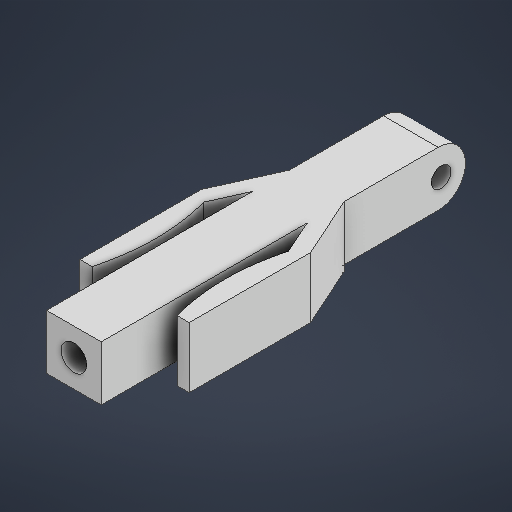
# Autodesk Inventor part: Upper leg connector to UL Ring_4
Saved by Autodesk Inventor 2027 (Build 310192060, 192F)
## iProperties
Created: 2026-07-03
Part Number: Upper leg connector to UL Ring_4
Material: Generic
Document SubType Name: Modeling
Designer: troop
Density: 1 g/cm^3
Appearance: Default
Author: troop
Autodesk Inventor part; units mm, degrees
ref_plane "YZ Plane" through (0, 0, 0) normal (1, 0, 0) x (0, 1, 0)
ref_plane "XZ Plane" through (0, 0, 0) normal (0, 1, 0) x (-1, 0, 0)
ref_plane "XY Plane" through (0, 0, 0) normal (0, 0, 1) x (1, 0, 0)
sketch "Sketch1" plane through (0, 0, 0) normal (0, 0, 1) x (1, 0, 0)
  line L0 (0, 0) -> (11.43, 0)
  line L1 (11.43, 0) -> (11.43, 11.43)
  line L2 (11.43, 11.43) -> (0, 11.43)
  line L3 (0, 11.43) -> (0, 0)
  dimension "d0" = 11.43
  dimension "d1" = 11.43
  constraints: 8 end point, 2 parallel, 1 horizontal, 1 perpendicular
  measures "d0" distance of L1.end L2.end
  measures "d1" distance of L0.end L1.end
extrude "Extrusion1" add sketch "Sketch1" along normal blind 76.2
sketch "Sketch2" plane through (0, 0, 76.2) normal (0, 0, 1) x (1, 0, 0)
  circle A0 centre (5.715, 5.715) radius 2.675
  line L0 (11.43, 0) -> (11.43, 11.43) projected
  line L1 (0, 0) -> (11.43, 0) projected
  dimension "d4" = 5.35
  dimension "d5" = 5.715
  dimension "d6" = 5.715
  constraints: 1 centre point
  measures "d4" diameter of A0
  measures "d5" distance from line of L0 A0.centre
  measures "d6" distance from line of L1 A0.centre
extrude "Extrusion2" cut sketch "Sketch2" against normal blind 50.8
sketch "Sketch3" plane through (11.43, 0, 0) normal (1, 0, 0) x (0, 0, -1)
  circle A0 centre (-5.08, 5.715) radius 2.05
  line L0 (0, 0) -> (0, 11.43) projected
  line L1 (0, 11.43) -> (-76.2, 11.43) projected
  dimension "d9" = 5.08
  dimension "d10" = 5.715
  dimension "d11" = 4.1
  constraints: 1 centre point
  measures "d9" distance from line of L0 A0.centre
  measures "d10" distance from line of L1 A0.centre
  measures "d11" diameter of A0
extrude "Extrusion3" cut sketch "Sketch3" against normal blind 50.8
fillet "Fillet1" radius 5.715 1 edges at (5.715, 11.43, 0)
fillet "Fillet2" radius 5.715 1 edges at (5.715, 0, 0)
sketch "Sketch4" plane through (0, 11.43, 76.2) normal (0, 1, 0) x (1, 0, 0)
  line L0 (0, 70.485) -> (0, 0) projected
  line L1 (0, 50.8) -> (-5.715, 38.1)
  line L2 (-5.715, 38.1) -> (-5.715, 12.7)
  line L3 (-5.715, 12.7) -> (-3.175, 12.7)
  line L4 (-3.175, 12.7) -> (-3.175, 36.0074)
  line L5 (-3.175, 36.0074) -> (0, 43.063)
  arc A0 (-3.175, 12.7) -> (-3.175, 36.0074) centre (-45.1557, 24.3537) ccw
  line L6 (11.43, 76.2) -> (0, 76.2) projected
  line L7 (0, 0) -> (11.43, 0) projected
  line L8 (11.43, 50.8) -> (17.145, 38.1)
  line L9 (17.145, 38.1) -> (17.145, 12.7)
  line L10 (17.145, 12.7) -> (14.605, 12.7)
  line L11 (14.605, 12.7) -> (14.605, 36.0074)
  line L12 (14.605, 36.0074) -> (11.43, 43.063)
  arc A1 (14.605, 36.0074) -> (14.605, 12.7) centre (56.5857, 24.3537) ccw
  line L13 (11.43, 70.485) -> (11.43, 0) projected
  point P0 (0, 76.2)
  point P1 (-3.175, 24.3537)
  point P2 (-1.5875, 24.3537)
  point P3 (14.605, 24.3537)
  point P4 (13.0175, 24.3537)
  point P5 (11.43, 35.2425)
  dimension "d16" = 25.4
  dimension "d17" = 12.7
  dimension "d22" = 38.1
  dimension "d24" = 2.54
  dimension "d26" = 3.175
  dimension "d27" = 3.175
  dimension "d28" = 1.5875
  dimension "d29" = 25.4
  dimension "d30" = 38.1
  dimension "d31" = 3.175
  dimension "d33" = 1.5875
  dimension "d34" = 25.4
  dimension "d35" = 2.54
  dimension "d36" = 7.737
  dimension "d37" = 12.7
  dimension "d38" = 180
  dimension "d39" = 3.175
  dimension "d40" = 3.175
  dimension "d43" = 23.3074
  constraints: 20 end point, 6 point on circle, 3 midpoint, 2 centre point, 2 point on line, 1 horizontal, 1 parallel, 1 vertical
  measures "d16" distance of point (0, 76.2) L1.start
  measures "d17" vertical distance of L0.end L2.end
  measures "d22" vertical distance of point (0, 76.2) L1.end
  measures "d24" distance of L2.end L3.end
  measures "d26" distance between parallel lines of L5 L1
  measures "d27" distance between parallel lines of L0 L4
  measures "d28" distance of point (-3.175, 24.354) point (-1.587, 24.354)
  measures "d29" distance of L6.start L8.start
  measures "d30" vertical distance of L6.start L9.start
  measures "d31" distance between parallel lines of L8 L12
  measures "d33" distance of point (14.605, 24.354) point (13.018, 24.354)
  measures "d34" distance of L9.start L9.end
  measures "d35" distance of L9.end L11.start
  measures "d36" distance of L12.start L12.end
  measures "d37" vertical distance of L8.start L9.start
  measures "d38" angle of L9 L11
  measures "d39" distance from line of L13 L11.start
  measures "d40" horizontal distance of point (11.43, 35.242) L12.start
  measures "d43" distance of L11.start L12.start
extrude "Extrusion4" add sketch "Sketch4" against normal blind 12.7
body "Solid1"
